Autodesk Inventor part; units mm, degrees
(part 2 of 2)
sketch "Sketch151" plane through (0, 0, 99) normal (0, 0, 1) x (1, 0, 0)
  circle A0 centre (215, 13.75) radius 3.2
  constraints: 1 centre point
extrude "Extrusion151" cut sketch "Sketch151" along normal blind 4
ref_plane "Work Plane152" through (0, 0, 99) normal (0, 0, 1) x (1, 0, 0)
sketch "Sketch152" plane through (0, 0, 99) normal (0, 0, 1) x (1, 0, 0)
  circle A0 centre (240, 13.75) radius 3.2
  constraints: 1 centre point
extrude "Extrusion152" cut sketch "Sketch152" along normal blind 4
ref_plane "Work Plane153" through (0, 0, 99) normal (0, 0, 1) x (1, 0, 0)
sketch "Sketch153" plane through (0, 0, 99) normal (0, 0, 1) x (1, 0, 0)
  circle A0 centre (265, 13.75) radius 3.2
  constraints: 1 centre point
extrude "Extrusion153" cut sketch "Sketch153" along normal blind 4
ref_plane "Work Plane154" through (0, 0, 99) normal (0, 0, 1) x (1, 0, 0)
sketch "Sketch154" plane through (0, 0, 99) normal (0, 0, 1) x (1, 0, 0)
  circle A0 centre (290, 13.75) radius 3.2
  constraints: 1 centre point
extrude "Extrusion154" cut sketch "Sketch154" along normal blind 4
ref_plane "Work Plane155" through (0, 0, 99) normal (0, 0, 1) x (1, 0, 0)
sketch "Sketch155" plane through (0, 0, 99) normal (0, 0, 1) x (1, 0, 0)
  circle A0 centre (315, 13.75) radius 3.2
  constraints: 1 centre point
extrude "Extrusion155" cut sketch "Sketch155" along normal blind 4
ref_plane "Work Plane156" through (0, 0, 100) normal (0, 0, 1) x (1, 0, 0)
sketch "Sketch156" plane through (0, 0, 100) normal (0, 0, 1) x (1, 0, 0)
  line L0 (100, 225) -> (350, 225)
  line L1 (350, 225) -> (350, 250)
  line L2 (350, 250) -> (100, 250)
  line L3 (100, 250) -> (100, 225)
  constraints: 8 end point, 2 parallel, 1 horizontal, 1 perpendicular
extrude "Extrusion156" add sketch "Sketch156" along normal blind 2
ref_plane "Work Plane157" through (0, 0, 100) normal (0, 0, 1) x (1, 0, 0)
sketch "Sketch157" plane through (0, 0, 100) normal (0, 0, 1) x (1, 0, 0)
  line L0 (100, 225) -> (350, 225)
  line L1 (350, 225) -> (350, 227)
  line L2 (350, 227) -> (100, 227)
  line L3 (100, 227) -> (100, 225)
  constraints: 8 end point, 2 parallel, 1 horizontal, 1 perpendicular
extrude "Extrusion157" add sketch "Sketch157" along normal blind 25
ref_plane "Work Plane158" through (0, 0, 99) normal (0, 0, 1) x (1, 0, 0)
sketch "Sketch158" plane through (0, 0, 99) normal (0, 0, 1) x (1, 0, 0)
  circle A0 centre (115, 238.75) radius 3.2
  constraints: 1 centre point
extrude "Extrusion158" cut sketch "Sketch158" along normal blind 4
ref_plane "Work Plane159" through (0, 0, 99) normal (0, 0, 1) x (1, 0, 0)
sketch "Sketch159" plane through (0, 0, 99) normal (0, 0, 1) x (1, 0, 0)
  circle A0 centre (140, 238.75) radius 3.2
  constraints: 1 centre point
extrude "Extrusion159" cut sketch "Sketch159" along normal blind 4
ref_plane "Work Plane160" through (0, 0, 99) normal (0, 0, 1) x (1, 0, 0)
sketch "Sketch160" plane through (0, 0, 99) normal (0, 0, 1) x (1, 0, 0)
  circle A0 centre (165, 238.75) radius 3.2
  constraints: 1 centre point
extrude "Extrusion160" cut sketch "Sketch160" along normal blind 4
ref_plane "Work Plane161" through (0, 0, 99) normal (0, 0, 1) x (1, 0, 0)
sketch "Sketch161" plane through (0, 0, 99) normal (0, 0, 1) x (1, 0, 0)
  circle A0 centre (190, 238.75) radius 3.2
  constraints: 1 centre point
extrude "Extrusion161" cut sketch "Sketch161" along normal blind 4
ref_plane "Work Plane162" through (0, 0, 99) normal (0, 0, 1) x (1, 0, 0)
sketch "Sketch162" plane through (0, 0, 99) normal (0, 0, 1) x (1, 0, 0)
  circle A0 centre (215, 238.75) radius 3.2
  constraints: 1 centre point
extrude "Extrusion162" cut sketch "Sketch162" along normal blind 4
ref_plane "Work Plane163" through (0, 0, 99) normal (0, 0, 1) x (1, 0, 0)
sketch "Sketch163" plane through (0, 0, 99) normal (0, 0, 1) x (1, 0, 0)
  circle A0 centre (240, 238.75) radius 3.2
  constraints: 1 centre point
extrude "Extrusion163" cut sketch "Sketch163" along normal blind 4
ref_plane "Work Plane164" through (0, 0, 99) normal (0, 0, 1) x (1, 0, 0)
sketch "Sketch164" plane through (0, 0, 99) normal (0, 0, 1) x (1, 0, 0)
  circle A0 centre (265, 238.75) radius 3.2
  constraints: 1 centre point
extrude "Extrusion164" cut sketch "Sketch164" along normal blind 4
ref_plane "Work Plane165" through (0, 0, 99) normal (0, 0, 1) x (1, 0, 0)
sketch "Sketch165" plane through (0, 0, 99) normal (0, 0, 1) x (1, 0, 0)
  circle A0 centre (290, 238.75) radius 3.2
  constraints: 1 centre point
extrude "Extrusion165" cut sketch "Sketch165" along normal blind 4
ref_plane "Work Plane166" through (0, 0, 99) normal (0, 0, 1) x (1, 0, 0)
sketch "Sketch166" plane through (0, 0, 99) normal (0, 0, 1) x (1, 0, 0)
  circle A0 centre (315, 238.75) radius 3.2
  constraints: 1 centre point
extrude "Extrusion166" cut sketch "Sketch166" along normal blind 4
ref_plane "Work Plane167" through (0, 0, 75) normal (0, 0, 1) x (1, 0, 0)
sketch "Sketch167" plane through (0, 0, 75) normal (0, 0, 1) x (1, 0, 0)
  line L0 (325, 0) -> (350, 0)
  line L1 (350, 0) -> (350, 2)
  line L2 (350, 2) -> (325, 2)
  line L3 (325, 2) -> (325, 0)
  constraints: 8 end point, 2 parallel, 1 horizontal, 1 perpendicular
extrude "Extrusion167" add sketch "Sketch167" along normal blind 50
ref_plane "Work Plane168" through (0, 0, 75) normal (0, 0, 1) x (1, 0, 0)
sketch "Sketch168" plane through (0, 0, 75) normal (0, 0, 1) x (1, 0, 0)
  line L0 (325, 0) -> (327, 0)
  line L1 (327, 0) -> (327, 25)
  line L2 (327, 25) -> (325, 25)
  line L3 (325, 25) -> (325, 0)
  constraints: 8 end point, 2 parallel, 1 horizontal, 1 perpendicular
extrude "Extrusion168" add sketch "Sketch168" along normal blind 50
ref_plane "Work Plane169" through (0, 0, 75) normal (0, 0, 1) x (1, 0, 0)
sketch "Sketch169" plane through (0, 0, 75) normal (0, 0, 1) x (1, 0, 0)
  line L0 (325, 225) -> (350, 225)
  line L1 (350, 225) -> (350, 227)
  line L2 (350, 227) -> (325, 227)
  line L3 (325, 227) -> (325, 225)
  constraints: 8 end point, 2 parallel, 1 horizontal, 1 perpendicular
extrude "Extrusion169" add sketch "Sketch169" along normal blind 50
ref_plane "Work Plane170" through (0, 0, 75) normal (0, 0, 1) x (1, 0, 0)
sketch "Sketch170" plane through (0, 0, 75) normal (0, 0, 1) x (1, 0, 0)
  line L0 (325, 225) -> (327, 225)
  line L1 (327, 225) -> (327, 250)
  line L2 (327, 250) -> (325, 250)
  line L3 (325, 250) -> (325, 225)
  constraints: 8 end point, 2 parallel, 1 horizontal, 1 perpendicular
extrude "Extrusion170" add sketch "Sketch170" along normal blind 50
ref_plane "Work Plane171" through (0, 0, 100) normal (0, 0, 1) x (1, 0, 0)
sketch "Sketch171" plane through (0, 0, 100) normal (0, 0, 1) x (1, 0, 0)
  line L0 (325, 0) -> (350, 0)
  line L1 (350, 0) -> (350, 250)
  line L2 (350, 250) -> (325, 250)
  line L3 (325, 250) -> (325, 0)
  constraints: 8 end point, 2 parallel, 1 horizontal, 1 perpendicular
extrude "Extrusion171" add sketch "Sketch171" along normal blind 2
ref_plane "Work Plane172" through (0, 0, 100) normal (0, 0, 1) x (1, 0, 0)
sketch "Sketch172" plane through (0, 0, 100) normal (0, 0, 1) x (1, 0, 0)
  line L0 (325, 0) -> (327, 0)
  line L1 (327, 0) -> (327, 250)
  line L2 (327, 250) -> (325, 250)
  line L3 (325, 250) -> (325, 0)
  constraints: 8 end point, 2 parallel, 1 horizontal, 1 perpendicular
extrude "Extrusion172" add sketch "Sketch172" along normal blind 25
body "Solid1"
